Autodesk Fusion 360 part; units mm, degrees
(part 16 of 28)
  line L828 (140.495, -16.335) -> (140.495, -17.235)
  line L829 (140.045, -16.785) -> (140.945, -16.785)
  line L830 (143.9337, -15.6998) -> (144.1242, -15.6998)
  line L831 (144.1242, -15.6998) -> (144.3147, -15.7951)
  line L832 (144.3147, -15.7951) -> (144.4099, -15.8903)
  line L833 (144.4099, -15.8903) -> (144.5051, -16.0808)
  line L834 (144.5051, -16.0808) -> (144.6004, -16.4617)
  line L835 (144.6004, -16.4617) -> (144.6004, -16.9379)
  line L836 (144.6004, -16.9379) -> (144.5051, -17.3189)
  line L837 (144.5051, -17.3189) -> (144.4099, -17.5094)
  line L838 (144.4099, -17.5094) -> (144.3147, -17.6046)
  line L839 (144.3147, -17.6046) -> (144.1242, -17.6998)
  line L840 (144.1242, -17.6998) -> (143.9337, -17.6998)
  line L841 (143.9337, -17.6998) -> (143.7432, -17.6046)
  line L842 (143.7432, -17.6046) -> (143.648, -17.5094)
  line L843 (143.648, -17.5094) -> (143.5528, -17.3189)
  line L844 (143.5528, -17.3189) -> (143.4575, -16.9379)
  line L845 (143.4575, -16.9379) -> (143.4575, -16.4617)
  line L846 (143.4575, -16.4617) -> (143.5528, -16.0808)
  line L847 (143.5528, -16.0808) -> (143.648, -15.8903)
  line L848 (143.648, -15.8903) -> (143.7432, -15.7951)
  line L849 (143.7432, -15.7951) -> (143.9337, -15.6998)
  line L850 (145.4575, -17.5094) -> (145.5528, -17.6046)
  line L851 (145.5528, -17.6046) -> (145.4575, -17.6998)
  line L852 (145.4575, -17.6998) -> (145.3623, -17.6046)
  line L853 (145.3623, -17.6046) -> (145.4575, -17.5094)
  line L854 (145.4575, -17.5094) -> (145.4575, -17.6998)
  line L855 (146.5051, -17.6998) -> (146.8861, -17.6998)
  line L856 (146.8861, -17.6998) -> (147.0766, -17.6046)
  line L857 (147.0766, -17.6046) -> (147.1718, -17.5094)
  line L858 (147.1718, -17.5094) -> (147.3623, -17.2236)
  line L859 (147.3623, -17.2236) -> (147.4575, -16.8427)
  line L860 (147.4575, -16.8427) -> (147.4575, -16.0808)
  line L861 (147.4575, -16.0808) -> (147.3623, -15.8903)
  line L862 (147.3623, -15.8903) -> (147.2671, -15.7951)
  line L863 (147.2671, -15.7951) -> (147.0766, -15.6998)
  line L864 (147.0766, -15.6998) -> (146.6956, -15.6998)
  line L865 (146.6956, -15.6998) -> (146.5051, -15.7951)
  line L866 (146.5051, -15.7951) -> (146.4099, -15.8903)
  line L867 (146.4099, -15.8903) -> (146.3147, -16.0808)
  line L868 (146.3147, -16.0808) -> (146.3147, -16.557)
  line L869 (146.3147, -16.557) -> (146.4099, -16.7475)
  line L870 (146.4099, -16.7475) -> (146.5051, -16.8427)
  line L871 (146.5051, -16.8427) -> (146.6956, -16.9379)
  line L872 (146.6956, -16.9379) -> (147.0766, -16.9379)
  line L873 (147.0766, -16.9379) -> (147.2671, -16.8427)
  line L874 (147.2671, -16.8427) -> (147.3623, -16.7475)
  line L875 (147.3623, -16.7475) -> (147.4575, -16.557)
  line L876 (148.6956, -15.6998) -> (148.8861, -15.6998)
  line L877 (148.8861, -15.6998) -> (149.0766, -15.7951)
  line L878 (149.0766, -15.7951) -> (149.1718, -15.8903)
  line L879 (149.1718, -15.8903) -> (149.2671, -16.0808)
  line L880 (149.2671, -16.0808) -> (149.3623, -16.4617)
  line L881 (149.3623, -16.4617) -> (149.3623, -16.9379)
  line L882 (149.3623, -16.9379) -> (149.2671, -17.3189)
  line L883 (149.2671, -17.3189) -> (149.1718, -17.5094)
  line L884 (149.1718, -17.5094) -> (149.0766, -17.6046)
  line L885 (149.0766, -17.6046) -> (148.8861, -17.6998)
  line L886 (148.8861, -17.6998) -> (148.6956, -17.6998)
  line L887 (148.6956, -17.6998) -> (148.5051, -17.6046)
  line L888 (148.5051, -17.6046) -> (148.4099, -17.5094)
  line L889 (148.4099, -17.5094) -> (148.3147, -17.3189)
  line L890 (148.3147, -17.3189) -> (148.2194, -16.9379)
  line L891 (148.2194, -16.9379) -> (148.2194, -16.4617)
  line L892 (148.2194, -16.4617) -> (148.3147, -16.0808)
  line L893 (148.3147, -16.0808) -> (148.4099, -15.8903)
  line L894 (148.4099, -15.8903) -> (148.5051, -15.7951)
  line L895 (148.5051, -15.7951) -> (148.6956, -15.6998)
  line L896 (150.6004, -15.6998) -> (150.7909, -15.6998)
  line L897 (150.7909, -15.6998) -> (150.9813, -15.7951)
  line L898 (150.9813, -15.7951) -> (151.0766, -15.8903)
  line L899 (151.0766, -15.8903) -> (151.1718, -16.0808)
  line L900 (151.1718, -16.0808) -> (151.2671, -16.4617)
  line L901 (151.2671, -16.4617) -> (151.2671, -16.9379)
  line L902 (151.2671, -16.9379) -> (151.1718, -17.3189)
  line L903 (151.1718, -17.3189) -> (151.0766, -17.5094)
  line L904 (151.0766, -17.5094) -> (150.9813, -17.6046)
  line L905 (150.9813, -17.6046) -> (150.7909, -17.6998)
  line L906 (150.7909, -17.6998) -> (150.6004, -17.6998)
  line L907 (150.6004, -17.6998) -> (150.4099, -17.6046)
  line L908 (150.4099, -17.6046) -> (150.3147, -17.5094)
  line L909 (150.3147, -17.5094) -> (150.2194, -17.3189)
  line L910 (150.2194, -17.3189) -> (150.1242, -16.9379)
  line L911 (150.1242, -16.9379) -> (150.1242, -16.4617)
  line L912 (150.1242, -16.4617) -> (150.2194, -16.0808)
  line L913 (150.2194, -16.0808) -> (150.3147, -15.8903)
  line L914 (150.3147, -15.8903) -> (150.4099, -15.7951)
  line L915 (150.4099, -15.7951) -> (150.6004, -15.6998)
  line L916 (152.1242, -17.6998) -> (152.1242, -16.3665)
  line L917 (152.1242, -16.557) -> (152.2194, -16.4617)
  line L918 (152.2194, -16.4617) -> (152.4099, -16.3665)
  line L919 (152.4099, -16.3665) -> (152.6956, -16.3665)
  line L920 (152.6956, -16.3665) -> (152.8861, -16.4617)
  line L921 (152.8861, -16.4617) -> (152.9813, -16.6522)
  line L922 (152.9813, -16.6522) -> (152.9813, -17.6998)
  line L923 (152.9813, -16.6522) -> (153.0766, -16.4617)
  line L924 (153.0766, -16.4617) -> (153.2671, -16.3665)
  line L925 (153.2671, -16.3665) -> (153.5528, -16.3665)
  line L926 (153.5528, -16.3665) -> (153.7432, -16.4617)
  line L927 (153.7432, -16.4617) -> (153.8385, -16.6522)
  line L928 (153.8385, -16.6522) -> (153.8385, -17.6998)
  line L929 (154.7909, -17.6998) -> (154.7909, -16.3665)
  line L930 (154.7909, -16.557) -> (154.8861, -16.4617)
  line L931 (154.8861, -16.4617) -> (155.0766, -16.3665)
  line L932 (155.0766, -16.3665) -> (155.3623, -16.3665)
  line L933 (155.3623, -16.3665) -> (155.5528, -16.4617)
  line L934 (155.5528, -16.4617) -> (155.648, -16.6522)
  line L935 (155.648, -16.6522) -> (155.648, -17.6998)
  line L936 (155.648, -16.6522) -> (155.7432, -16.4617)
  line L937 (155.7432, -16.4617) -> (155.9337, -16.3665)
  line L938 (155.9337, -16.3665) -> (156.2194, -16.3665)
  line L939 (156.2194, -16.3665) -> (156.4099, -16.4617)
  line L940 (156.4099, -16.4617) -> (156.5051, -16.6522)
  line L941 (156.5052, -16.6522) -> (156.5052, -17.6998)
  line L942 (160.4099, -15.6046) -> (158.6956, -18.176)
  line L943 (162.9813, -15.6998) -> (163.1718, -15.6998)
  line L944 (163.1718, -15.6998) -> (163.3623, -15.7951)
  line L945 (163.3623, -15.7951) -> (163.4575, -15.8903)
  line L946 (163.4575, -15.8903) -> (163.5528, -16.0808)
  line L947 (163.5528, -16.0808) -> (163.648, -16.4617)
  line L948 (163.648, -16.4617) -> (163.648, -16.9379)
  line L949 (163.648, -16.9379) -> (163.5528, -17.3189)
  line L950 (163.5528, -17.3189) -> (163.4575, -17.5094)
  line L951 (163.4575, -17.5094) -> (163.3623, -17.6046)
  line L952 (163.3623, -17.6046) -> (163.1718, -17.6998)
  line L953 (163.1718, -17.6998) -> (162.9813, -17.6998)
  line L954 (162.9813, -17.6998) -> (162.7909, -17.6046)
  line L955 (162.7909, -17.6046) -> (162.6956, -17.5094)
  line L956 (162.6956, -17.5094) -> (162.6004, -17.3189)
  line L957 (162.6004, -17.3189) -> (162.5052, -16.9379)
  line L958 (162.5052, -16.9379) -> (162.5052, -16.4617)
  line L959 (162.5052, -16.4617) -> (162.6004, -16.0808)
  line L960 (162.6004, -16.0808) -> (162.6956, -15.8903)
  line L961 (162.6956, -15.8903) -> (162.7909, -15.7951)
  line L962 (162.7909, -15.7951) -> (162.9813, -15.6998)
  line L963 (164.5052, -17.5094) -> (164.6004, -17.6046)
  line L964 (164.6004, -17.6046) -> (164.5052, -17.6998)
  line L965 (164.5052, -17.6998) -> (164.4099, -17.6046)
  line L966 (164.4099, -17.6046) -> (164.5052, -17.5094)
  line L967 (164.5052, -17.5094) -> (164.5052, -17.6998)
  line L968 (165.8385, -15.6998) -> (166.029, -15.6998)
  line L969 (166.029, -15.6998) -> (166.2194, -15.7951)
  line L970 (166.2194, -15.7951) -> (166.3147, -15.8903)
  line L971 (166.3147, -15.8903) -> (166.4099, -16.0808)
  line L972 (166.4099, -16.0808) -> (166.5052, -16.4617)
  line L973 (166.5052, -16.4617) -> (166.5052, -16.9379)
  line L974 (166.5052, -16.9379) -> (166.4099, -17.3189)
  line L975 (166.4099, -17.3189) -> (166.3147, -17.5094)
  line L976 (166.3147, -17.5094) -> (166.2194, -17.6046)
  line L977 (166.2194, -17.6046) -> (166.029, -17.6998)
  line L978 (166.029, -17.6998) -> (165.8385, -17.6998)
  line L979 (165.8385, -17.6998) -> (165.648, -17.6046)
  line L980 (165.648, -17.6046) -> (165.5528, -17.5094)
  line L981 (165.5528, -17.5094) -> (165.4575, -17.3189)
  line L982 (165.4575, -17.3189) -> (165.3623, -16.9379)
  line L983 (165.3623, -16.9379) -> (165.3623, -16.4617)
  line L984 (165.3623, -16.4617) -> (165.4575, -16.0808)
  line L985 (165.4575, -16.0808) -> (165.5528, -15.8903)
  line L986 (165.5528, -15.8903) -> (165.648, -15.7951)
  line L987 (165.648, -15.7951) -> (165.8385, -15.6998)
  line L988 (167.1718, -15.6998) -> (168.4099, -15.6998)
  line L989 (168.4099, -15.6998) -> (167.7432, -16.4617)
  line L990 (167.7432, -16.4617) -> (168.029, -16.4617)
  line L991 (168.029, -16.4617) -> (168.2194, -16.557)
  line L992 (168.2194, -16.557) -> (168.3147, -16.6522)
  line L993 (168.3147, -16.6522) -> (168.4099, -16.8427)
  line L994 (168.4099, -16.8427) -> (168.4099, -17.3189)
  line L995 (168.4099, -17.3189) -> (168.3147, -17.5094)
  line L996 (168.3147, -17.5094) -> (168.2194, -17.6046)
  line L997 (168.2194, -17.6046) -> (168.029, -17.6998)
  line L998 (168.029, -17.6998) -> (167.4575, -17.6998)
  line L999 (167.4575, -17.6998) -> (167.2671, -17.6046)
  line L1000 (167.2671, -17.6046) -> (167.1718, -17.5094)
  line L1001 (170.2194, -15.6998) -> (169.2671, -15.6998)
  line L1002 (169.2671, -15.6998) -> (169.1718, -16.6522)
  line L1003 (169.1718, -16.6522) -> (169.2671, -16.557)
  line L1004 (169.2671, -16.557) -> (169.4575, -16.4617)
  line L1005 (169.4575, -16.4617) -> (169.9337, -16.4617)
  line L1006 (169.9337, -16.4617) -> (170.1242, -16.557)
  line L1007 (170.1242, -16.557) -> (170.2194, -16.6522)
  line L1008 (170.2194, -16.6522) -> (170.3147, -16.8427)
  line L1009 (170.3147, -16.8427) -> (170.3147, -17.3189)
  line L1010 (170.3147, -17.3189) -> (170.2194, -17.5094)
  line L1011 (170.2194, -17.5094) -> (170.1242, -17.6046)
  line L1012 (170.1242, -17.6046) -> (169.9337, -17.6998)
  line L1013 (169.9337, -17.6998) -> (169.4575, -17.6998)
  line L1014 (169.4575, -17.6998) -> (169.2671, -17.6046)
  line L1015 (169.2671, -17.6046) -> (169.1718, -17.5094)
  line L1016 (172.029, -16.3665) -> (172.029, -17.6998)
  line L1017 (171.5528, -15.6046) -> (171.0766, -17.0332)
  line L1018 (171.0766, -17.0332) -> (172.3147, -17.0332)
  line L1019 (172.9813, -15.6998) -> (172.9813, -16.0808)
  line L1020 (173.7432, -15.6998) -> (173.7432, -16.0808)
  line L1021 (176.6956, -18.4617) -> (176.6004, -18.3665)
  line L1022 (176.6004, -18.3665) -> (176.4099, -18.0808)
  line L1023 (176.4099, -18.0808) -> (176.3147, -17.8903)
  line L1024 (176.3147, -17.8903) -> (176.2194, -17.6046)
  line L1025 (176.2194, -17.6046) -> (176.1242, -17.1284)
  line L1026 (176.1242, -17.1284) -> (176.1242, -16.7475)
  line L1027 (176.1242, -16.7475) -> (176.2194, -16.2713)
  line L1028 (176.2194, -16.2713) -> (176.3147, -15.9856)
  line L1029 (176.3147, -15.9856) -> (176.4099, -15.7951)
  line L1030 (176.4099, -15.7951) -> (176.6004, -15.5094)
  line L1031 (176.6004, -15.5094) -> (176.6956, -15.4141)
  line L1032 (178.5052, -17.6998) -> (177.3623, -17.6998)
  line L1033 (177.9337, -17.6998) -> (177.9337, -15.6998)
  line L1034 (177.9337, -15.6998) -> (177.7432, -15.9856)
  line L1035 (177.7432, -15.9856) -> (177.5528, -16.176)
  line L1036 (177.5528, -16.176) -> (177.3623, -16.2713)
  line L1037 (179.2671, -15.8903) -> (179.3623, -15.7951)
  line L1038 (179.3623, -15.7951) -> (179.5528, -15.6998)
  line L1039 (179.5528, -15.6998) -> (180.029, -15.6998)
  line L1040 (180.029, -15.6998) -> (180.2194, -15.7951)
  line L1041 (180.2194, -15.7951) -> (180.3147, -15.8903)
  line L1042 (180.3147, -15.8903) -> (180.4099, -16.0808)
  line L1043 (180.4099, -16.0808) -> (180.4099, -16.2713)
  line L1044 (180.4099, -16.2713) -> (180.3147, -16.557)
  line L1045 (180.3147, -16.557) -> (179.1718, -17.6998)
  line L1046 (179.1718, -17.6998) -> (180.4099, -17.6998)
  line L1047 (182.7909, -17.6998) -> (182.7909, -15.6998)
  line L1048 (183.648, -17.6998) -> (183.648, -16.6522)
  line L1049 (183.648, -16.6522) -> (183.5528, -16.4617)
  line L1050 (183.5528, -16.4617) -> (183.3623, -16.3665)
  line L1051 (183.3623, -16.3665) -> (183.0766, -16.3665)
  line L1052 (183.0766, -16.3665) -> (182.8861, -16.4617)
  line L1053 (182.8861, -16.4617) -> (182.7909, -16.557)
  line L1054 (184.8861, -17.6998) -> (184.6956, -17.6046)
  line L1055 (184.6956, -17.6046) -> (184.6004, -17.5094)
  line L1056 (184.6004, -17.5094) -> (184.5052, -17.3189)
  line L1057 (184.5052, -17.3189) -> (184.5052, -16.7475)
  line L1058 (184.5052, -16.7475) -> (184.6004, -16.557)
  line L1059 (184.6004, -16.557) -> (184.6956, -16.4617)
  line L1060 (184.6956, -16.4617) -> (184.8861, -16.3665)
  line L1061 (184.8861, -16.3665) -> (185.1718, -16.3665)
  line L1062 (185.1718, -16.3665) -> (185.3623, -16.4617)
  line L1063 (185.3623, -16.4617) -> (185.4575, -16.557)
  line L1064 (185.4575, -16.557) -> (185.5528, -16.7475)
  line L1065 (185.5528, -16.7475) -> (185.5528, -17.3189)
  line L1066 (185.5528, -17.3189) -> (185.4575, -17.5094)
  line L1067 (185.4575, -17.5094) -> (185.3623, -17.6046)
  line L1068 (185.3623, -17.6046) -> (185.1718, -17.6998)
  line L1069 (185.1718, -17.6998) -> (184.8861, -17.6998)
  line L1070 (186.6956, -17.6998) -> (186.5052, -17.6046)
  line L1071 (186.5052, -17.6046) -> (186.4099, -17.4141)
  line L1072 (186.4099, -17.4141) -> (186.4099, -15.6998)
  line L1073 (188.2194, -17.6046) -> (188.029, -17.6998)
  line L1074 (188.029, -17.6998) -> (187.648, -17.6998)
  line L1075 (187.648, -17.6998) -> (187.4575, -17.6046)
  line L1076 (187.4575, -17.6046) -> (187.3623, -17.4141)
  line L1077 (187.3623, -17.4141) -> (187.3623, -16.6522)
  line L1078 (187.3623, -16.6522) -> (187.4575, -16.4617)
  line L1079 (187.4575, -16.4617) -> (187.648, -16.3665)
  line L1080 (187.648, -16.3665) -> (188.029, -16.3665)
  line L1081 (188.029, -16.3665) -> (188.2194, -16.4617)
  line L1082 (188.2194, -16.4617) -> (188.3147, -16.6522)
  line L1083 (188.3147, -16.6522) -> (188.3147, -16.8427)
  line L1084 (188.3147, -16.8427) -> (187.3623, -17.0332)
  line L1085 (189.0766, -17.6046) -> (189.2671, -17.6998)
  line L1086 (189.2671, -17.6998) -> (189.648, -17.6998)
  line L1087 (189.648, -17.6998) -> (189.8385, -17.6046)
  line L1088 (189.8385, -17.6046) -> (189.9337, -17.4141)
  line L1089 (189.9337, -17.4141) -> (189.9337, -17.3189)
  line L1090 (189.9337, -17.3189) -> (189.8385, -17.1284)
  line L1091 (189.8385, -17.1284) -> (189.648, -17.0332)
  line L1092 (189.648, -17.0332) -> (189.3623, -17.0332)
  line L1093 (189.3623, -17.0332) -> (189.1718, -16.9379)
  line L1094 (189.1718, -16.9379) -> (189.0766, -16.7475)
  line L1095 (189.0766, -16.7475) -> (189.0766, -16.6522)
  line L1096 (189.0766, -16.6522) -> (189.1718, -16.4617)
  line L1097 (189.1718, -16.4617) -> (189.3623, -16.3665)
  line L1098 (189.3623, -16.3665) -> (189.648, -16.3665)
  line L1099 (189.648, -16.3665) -> (189.8385, -16.4617)
  line L1100 (190.6004, -18.4617) -> (190.6956, -18.3665)
  line L1101 (190.6956, -18.3665) -> (190.8861, -18.0808)
  line L1102 (190.8861, -18.0808) -> (190.9813, -17.8903)
  line L1103 (190.9813, -17.8903) -> (191.0766, -17.6046)
  line L1104 (191.0766, -17.6046) -> (191.1718, -17.1284)
  line L1105 (191.1718, -17.1284) -> (191.1718, -16.7475)
  line L1106 (191.1718, -16.7475) -> (191.0766, -16.2713)
  line L1107 (191.0766, -16.2713) -> (190.9813, -15.9856)
  line L1108 (190.9813, -15.9856) -> (190.8861, -15.7951)
  line L1109 (190.8861, -15.7951) -> (190.6956, -15.5094)
  line L1110 (190.6956, -15.5094) -> (190.6004, -15.4141)
  line L1111 (140.7986, -19.7786) -> (140.7986, -19.0714)
  line L1112 (140.7986, -19.0714) -> (140.0914, -19.0714)
  line L1113 (140.0914, -19.0714) -> (140.0914, -19.7786)
  line L1114 (140.0914, -19.7786) -> (140.7986, -19.7786)
  line L1115 (144.6004, -20.3398) -> (143.4575, -20.3398)
  line L1116 (144.029, -20.3398) -> (144.029, -18.3398)
  line L1117 (144.029, -18.3398) -> (143.8385, -18.6256)
  line L1118 (143.8385, -18.6256) -> (143.648, -18.816)
  line L1119 (143.648, -18.816) -> (143.4575, -18.9113)
  line L1120 (145.4575, -20.1494) -> (145.5528, -20.2446)
  line L1121 (145.5528, -20.2446) -> (145.4575, -20.3398)
  line L1122 (145.4575, -20.3398) -> (145.3623, -20.2446)
  line L1123 (145.3623, -20.2446) -> (145.4575, -20.1494)
  line L1124 (145.4575, -20.1494) -> (145.4575, -20.3398)
  line L1125 (146.7909, -18.3398) -> (146.9813, -18.3398)
  line L1126 (146.9813, -18.3398) -> (147.1718, -18.4351)
  line L1127 (147.1718, -18.4351) -> (147.2671, -18.5303)
  line L1128 (147.2671, -18.5303) -> (147.3623, -18.7208)
  line L1129 (147.3623, -18.7208) -> (147.4575, -19.1017)
  line L1130 (147.4575, -19.1017) -> (147.4575, -19.5779)
  line L1131 (147.4575, -19.5779) -> (147.3623, -19.9589)
  line L1132 (147.3623, -19.9589) -> (147.2671, -20.1494)
  line L1133 (147.2671, -20.1494) -> (147.1718, -20.2446)
  line L1134 (147.1718, -20.2446) -> (146.9813, -20.3398)
  line L1135 (146.9813, -20.3398) -> (146.7909, -20.3398)
  line L1136 (146.7909, -20.3398) -> (146.6004, -20.2446)
  line L1137 (146.6004, -20.2446) -> (146.5051, -20.1494)
  line L1138 (146.5051, -20.1494) -> (146.4099, -19.9589)
  line L1139 (146.4099, -19.9589) -> (146.3147, -19.5779)
  line L1140 (146.3147, -19.5779) -> (146.3147, -19.1017)
  line L1141 (146.3147, -19.1017) -> (146.4099, -18.7208)
  line L1142 (146.4099, -18.7208) -> (146.5051, -18.5303)
  line L1143 (146.5051, -18.5303) -> (146.6004, -18.4351)
  line L1144 (146.6004, -18.4351) -> (146.7909, -18.3398)
  line L1145 (148.6956, -18.3398) -> (148.8861, -18.3398)
  line L1146 (148.8861, -18.3398) -> (149.0766, -18.4351)
  line L1147 (149.0766, -18.4351) -> (149.1718, -18.5303)
  line L1148 (149.1718, -18.5303) -> (149.2671, -18.7208)
  line L1149 (149.2671, -18.7208) -> (149.3623, -19.1017)
  line L1150 (149.3623, -19.1017) -> (149.3623, -19.5779)
  line L1151 (149.3623, -19.5779) -> (149.2671, -19.9589)
  line L1152 (149.2671, -19.9589) -> (149.1718, -20.1494)
  line L1153 (149.1718, -20.1494) -> (149.0766, -20.2446)
  line L1154 (149.0766, -20.2446) -> (148.8861, -20.3398)
  line L1155 (148.8861, -20.3398) -> (148.6956, -20.3398)
  line L1156 (148.6956, -20.3398) -> (148.5051, -20.2446)
  line L1157 (148.5051, -20.2446) -> (148.4099, -20.1494)
  line L1158 (148.4099, -20.1494) -> (148.3147, -19.9589)
  line L1159 (148.3147, -19.9589) -> (148.2194, -19.5779)
  line L1160 (148.2194, -19.5779) -> (148.2194, -19.1017)
  line L1161 (148.2194, -19.1017) -> (148.3147, -18.7208)
  line L1162 (148.3147, -18.7208) -> (148.4099, -18.5303)
  line L1163 (148.4099, -18.5303) -> (148.5051, -18.4351)
  line L1164 (148.5051, -18.4351) -> (148.6956, -18.3398)
  line L1165 (150.6004, -18.3398) -> (150.7909, -18.3398)
  line L1166 (150.7909, -18.3398) -> (150.9813, -18.4351)
  line L1167 (150.9813, -18.4351) -> (151.0766, -18.5303)
  line L1168 (151.0766, -18.5303) -> (151.1718, -18.7208)
  line L1169 (151.1718, -18.7208) -> (151.2671, -19.1017)
  line L1170 (151.2671, -19.1017) -> (151.2671, -19.5779)
  line L1171 (151.2671, -19.5779) -> (151.1718, -19.9589)
  line L1172 (151.1718, -19.9589) -> (151.0766, -20.1494)
  line L1173 (151.0766, -20.1494) -> (150.9813, -20.2446)
  line L1174 (150.9813, -20.2446) -> (150.7909, -20.3398)
  line L1175 (150.7909, -20.3398) -> (150.6004, -20.3398)
  line L1176 (150.6004, -20.3398) -> (150.4099, -20.2446)
  line L1177 (150.4099, -20.2446) -> (150.3147, -20.1494)
  line L1178 (150.3147, -20.1494) -> (150.2194, -19.9589)
  line L1179 (150.2194, -19.9589) -> (150.1242, -19.5779)
  line L1180 (150.1242, -19.5779) -> (150.1242, -19.1017)
  line L1181 (150.1242, -19.1017) -> (150.2194, -18.7208)
  line L1182 (150.2194, -18.7208) -> (150.3147, -18.5303)
  line L1183 (150.3147, -18.5303) -> (150.4099, -18.4351)
  line L1184 (150.4099, -18.4351) -> (150.6004, -18.3398)
  line L1185 (152.1242, -20.3398) -> (152.1242, -19.0065)
  line L1186 (152.1242, -19.197) -> (152.2194, -19.1017)
  line L1187 (152.2194, -19.1017) -> (152.4099, -19.0065)
  line L1188 (152.4099, -19.0065) -> (152.6956, -19.0065)
  line L1189 (152.6956, -19.0065) -> (152.8861, -19.1017)
  line L1190 (152.8861, -19.1017) -> (152.9813, -19.2922)
  line L1191 (152.9813, -19.2922) -> (152.9813, -20.3398)
  line L1192 (152.9813, -19.2922) -> (153.0766, -19.1017)
  line L1193 (153.0766, -19.1017) -> (153.2671, -19.0065)
  line L1194 (153.2671, -19.0065) -> (153.5528, -19.0065)
  line L1195 (153.5528, -19.0065) -> (153.7432, -19.1017)
  line L1196 (153.7432, -19.1017) -> (153.8385, -19.2922)
  line L1197 (153.8385, -19.2922) -> (153.8385, -20.3398)
  line L1198 (154.7909, -20.3398) -> (154.7909, -19.0065)
  line L1199 (154.7909, -19.197) -> (154.8861, -19.1017)
  line L1200 (154.8861, -19.1017) -> (155.0766, -19.0065)
  line L1201 (155.0766, -19.0065) -> (155.3623, -19.0065)
  line L1202 (155.3623, -19.0065) -> (155.5528, -19.1017)
  line L1203 (155.5528, -19.1017) -> (155.648, -19.2922)
  line L1204 (155.648, -19.2922) -> (155.648, -20.3398)
  line L1205 (155.648, -19.2922) -> (155.7432, -19.1017)
  line L1206 (155.7432, -19.1017) -> (155.9337, -19.0065)
  line L1207 (155.9337, -19.0065) -> (156.2194, -19.0065)
  line L1208 (156.2194, -19.0065) -> (156.4099, -19.1017)
  line L1209 (156.4099, -19.1017) -> (156.5051, -19.2922)
  line L1210 (156.5052, -19.2922) -> (156.5052, -20.3398)
  line L1211 (160.4099, -18.2446) -> (158.6956, -20.816)
  line L1212 (162.9813, -18.3398) -> (163.1718, -18.3398)
  line L1213 (163.1718, -18.3398) -> (163.3623, -18.4351)
  line L1214 (163.3623, -18.4351) -> (163.4575, -18.5303)
  line L1215 (163.4575, -18.5303) -> (163.5528, -18.7208)
  line L1216 (163.5528, -18.7208) -> (163.648, -19.1017)
  line L1217 (163.648, -19.1017) -> (163.648, -19.5779)
  line L1218 (163.648, -19.5779) -> (163.5528, -19.9589)
  line L1219 (163.5528, -19.9589) -> (163.4575, -20.1494)
  line L1220 (163.4575, -20.1494) -> (163.3623, -20.2446)
  line L1221 (163.3623, -20.2446) -> (163.1718, -20.3398)
  line L1222 (163.1718, -20.3398) -> (162.9813, -20.3398)
  line L1223 (162.9813, -20.3398) -> (162.7909, -20.2446)
  line L1224 (162.7909, -20.2446) -> (162.6956, -20.1494)
  line L1225 (162.6956, -20.1494) -> (162.6004, -19.9589)
  line L1226 (162.6004, -19.9589) -> (162.5052, -19.5779)
  line L1227 (162.5052, -19.5779) -> (162.5052, -19.1017)
  line L1228 (162.5052, -19.1017) -> (162.6004, -18.7208)
  line L1229 (162.6004, -18.7208) -> (162.6956, -18.5303)
  line L1230 (162.6956, -18.5303) -> (162.7909, -18.4351)
  line L1231 (162.7909, -18.4351) -> (162.9813, -18.3398)
  line L1232 (164.5052, -20.1494) -> (164.6004, -20.2446)
  line L1233 (164.6004, -20.2446) -> (164.5052, -20.3398)
  line L1234 (164.5052, -20.3398) -> (164.4099, -20.2446)
  line L1235 (164.4099, -20.2446) -> (164.5052, -20.1494)
  line L1236 (164.5052, -20.1494) -> (164.5052, -20.3398)
  line L1237 (165.8385, -18.3398) -> (166.029, -18.3398)
  line L1238 (166.029, -18.3398) -> (166.2194, -18.4351)
  line L1239 (166.2194, -18.4351) -> (166.3147, -18.5303)
  line L1240 (166.3147, -18.5303) -> (166.4099, -18.7208)
  line L1241 (166.4099, -18.7208) -> (166.5052, -19.1017)
  line L1242 (166.5052, -19.1017) -> (166.5052, -19.5779)
  line L1243 (166.5052, -19.5779) -> (166.4099, -19.9589)
  line L1244 (166.4099, -19.9589) -> (166.3147, -20.1494)
  line L1245 (166.3147, -20.1494) -> (166.2194, -20.2446)
  line L1246 (166.2194, -20.2446) -> (166.029, -20.3398)
  line L1247 (166.029, -20.3398) -> (165.8385, -20.3398)
  line L1248 (165.8385, -20.3398) -> (165.648, -20.2446)
  line L1249 (165.648, -20.2446) -> (165.5528, -20.1494)
  line L1250 (165.5528, -20.1494) -> (165.4575, -19.9589)
  line L1251 (165.4575, -19.9589) -> (165.3623, -19.5779)
  line L1252 (165.3623, -19.5779) -> (165.3623, -19.1017)
  line L1253 (165.3623, -19.1017) -> (165.4575, -18.7208)
  line L1254 (165.4575, -18.7208) -> (165.5528, -18.5303)
  line L1255 (165.5528, -18.5303) -> (165.648, -18.4351)
  line L1256 (165.648, -18.4351) -> (165.8385, -18.3398)
  line L1257 (167.1718, -18.3398) -> (168.4099, -18.3398)
  line L1258 (168.4099, -18.3398) -> (167.7432, -19.1017)
  line L1259 (167.7432, -19.1017) -> (168.029, -19.1017)
  line L1260 (168.029, -19.1017) -> (168.2194, -19.197)
  line L1261 (168.2194, -19.197) -> (168.3147, -19.2922)
  line L1262 (168.3147, -19.2922) -> (168.4099, -19.4827)
  line L1263 (168.4099, -19.4827) -> (168.4099, -19.9589)
  line L1264 (168.4099, -19.9589) -> (168.3147, -20.1494)
  line L1265 (168.3147, -20.1494) -> (168.2194, -20.2446)
  line L1266 (168.2194, -20.2446) -> (168.029, -20.3398)
  line L1267 (168.029, -20.3398) -> (167.4575, -20.3398)
  line L1268 (167.4575, -20.3398) -> (167.2671, -20.2446)
  line L1269 (167.2671, -20.2446) -> (167.1718, -20.1494)
  line L1270 (169.3623, -20.3398) -> (169.7432, -20.3398)
  line L1271 (169.7432, -20.3398) -> (169.9337, -20.2446)
  line L1272 (169.9337, -20.2446) -> (170.029, -20.1494)
  line L1273 (170.029, -20.1494) -> (170.2194, -19.8636)
  line L1274 (170.2194, -19.8636) -> (170.3147, -19.4827)
  line L1275 (170.3147, -19.4827) -> (170.3147, -18.7208)
  line L1276 (170.3147, -18.7208) -> (170.2194, -18.5303)
  line L1277 (170.2194, -18.5303) -> (170.1242, -18.4351)
  line L1278 (170.1242, -18.4351) -> (169.9337, -18.3398)
  line L1279 (169.9337, -18.3398) -> (169.5528, -18.3398)
  line L1280 (169.5528, -18.3398) -> (169.3623, -18.4351)
  line L1281 (169.3623, -18.4351) -> (169.2671, -18.5303)
  line L1282 (169.2671, -18.5303) -> (169.1718, -18.7208)
  line L1283 (169.1718, -18.7208) -> (169.1718, -19.197)
  line L1284 (169.1718, -19.197) -> (169.2671, -19.3875)
  line L1285 (169.2671, -19.3875) -> (169.3623, -19.4827)
  line L1286 (169.3623, -19.4827) -> (169.5528, -19.5779)
  line L1287 (169.5528, -19.5779) -> (169.9337, -19.5779)
  line L1288 (169.9337, -19.5779) -> (170.1242, -19.4827)
  line L1289 (170.1242, -19.4827) -> (170.2194, -19.3875)
  line L1290 (170.2194, -19.3875) -> (170.3147, -19.197)
  line L1291 (172.029, -19.0065) -> (172.029, -20.3398)
  line L1292 (171.5528, -18.2446) -> (171.0766, -19.6732)
  line L1293 (171.0766, -19.6732) -> (172.3147, -19.6732)
  line L1294 (172.9813, -18.3398) -> (172.9813, -18.7208)
  line L1295 (173.7432, -18.3398) -> (173.7432, -18.7208)
  line L1296 (176.6956, -21.1017) -> (176.6004, -21.0065)
  line L1297 (176.6004, -21.0065) -> (176.4099, -20.7208)
  line L1298 (176.4099, -20.7208) -> (176.3147, -20.5303)
  line L1299 (176.3147, -20.5303) -> (176.2194, -20.2446)
  line L1300 (176.2194, -20.2446) -> (176.1242, -19.7684)
  line L1301 (176.1242, -19.7684) -> (176.1242, -19.3875)
  line L1302 (176.1242, -19.3875) -> (176.2194, -18.9113)
  line L1303 (176.2194, -18.9113) -> (176.3147, -18.6256)
  line L1304 (176.3147, -18.6256) -> (176.4099, -18.4351)
  line L1305 (176.4099, -18.4351) -> (176.6004, -18.1494)
  line L1306 (176.6004, -18.1494) -> (176.6956, -18.0541)
  line L1307 (178.5052, -20.3398) -> (177.3623, -20.3398)
  line L1308 (177.9337, -20.3398) -> (177.9337, -18.3398)
  line L1309 (177.9337, -18.3398) -> (177.7432, -18.6256)
  line L1310 (177.7432, -18.6256) -> (177.5528, -18.816)
  line L1311 (177.5528, -18.816) -> (177.3623, -18.9113)
  line L1312 (179.2671, -18.5303) -> (179.3623, -18.4351)
  line L1313 (179.3623, -18.4351) -> (179.5528, -18.3398)
  line L1314 (179.5528, -18.3398) -> (180.029, -18.3398)
  line L1315 (180.029, -18.3398) -> (180.2194, -18.4351)
  line L1316 (180.2194, -18.4351) -> (180.3147, -18.5303)
  line L1317 (180.3147, -18.5303) -> (180.4099, -18.7208)
  line L1318 (180.4099, -18.7208) -> (180.4099, -18.9113)
  line L1319 (180.4099, -18.9113) -> (180.3147, -19.197)
  line L1320 (180.3147, -19.197) -> (179.1718, -20.3398)
  line L1321 (179.1718, -20.3398) -> (180.4099, -20.3398)
  line L1322 (182.7909, -20.3398) -> (182.7909, -18.3398)
  line L1323 (183.648, -20.3398) -> (183.648, -19.2922)
  line L1324 (183.648, -19.2922) -> (183.5528, -19.1017)
  line L1325 (183.5528, -19.1017) -> (183.3623, -19.0065)
  line L1326 (183.3623, -19.0065) -> (183.0766, -19.0065)
  line L1327 (183.0766, -19.0065) -> (182.8861, -19.1017)
  line L1328 (182.8861, -19.1017) -> (182.7909, -19.197)
  line L1329 (184.8861, -20.3398) -> (184.6956, -20.2446)
  line L1330 (184.6956, -20.2446) -> (184.6004, -20.1494)
  line L1331 (184.6004, -20.1494) -> (184.5052, -19.9589)
  line L1332 (184.5052, -19.9589) -> (184.5052, -19.3875)
  line L1333 (184.5052, -19.3875) -> (184.6004, -19.197)
  line L1334 (184.6004, -19.197) -> (184.6956, -19.1017)
  line L1335 (184.6956, -19.1017) -> (184.8861, -19.0065)
  line L1336 (184.8861, -19.0065) -> (185.1718, -19.0065)
  line L1337 (185.1718, -19.0065) -> (185.3623, -19.1017)
  line L1338 (185.3623, -19.1017) -> (185.4575, -19.197)
  line L1339 (185.4575, -19.197) -> (185.5528, -19.3875)
  line L1340 (185.5528, -19.3875) -> (185.5528, -19.9589)
  line L1341 (185.5528, -19.9589) -> (185.4575, -20.1494)
  line L1342 (185.4575, -20.1494) -> (185.3623, -20.2446)
  line L1343 (185.3623, -20.2446) -> (185.1718, -20.3398)
  line L1344 (185.1718, -20.3398) -> (184.8861, -20.3398)
  line L1345 (186.6956, -20.3398) -> (186.5052, -20.2446)
  line L1346 (186.5052, -20.2446) -> (186.4099, -20.0541)
  line L1347 (186.4099, -20.0541) -> (186.4099, -18.3398)
  line L1348 (188.2194, -20.2446) -> (188.029, -20.3398)
  line L1349 (188.029, -20.3398) -> (187.648, -20.3398)
  line L1350 (187.648, -20.3398) -> (187.4575, -20.2446)
  line L1351 (187.4575, -20.2446) -> (187.3623, -20.0541)
  line L1352 (187.3623, -20.0541) -> (187.3623, -19.2922)
  line L1353 (187.3623, -19.2922) -> (187.4575, -19.1017)
  line L1354 (187.4575, -19.1017) -> (187.648, -19.0065)
  line L1355 (187.648, -19.0065) -> (188.029, -19.0065)
  line L1356 (188.029, -19.0065) -> (188.2194, -19.1017)
  line L1357 (188.2194, -19.1017) -> (188.3147, -19.2922)
  line L1358 (188.3147, -19.2922) -> (188.3147, -19.4827)
  line L1359 (188.3147, -19.4827) -> (187.3623, -19.6732)
  line L1360 (189.0766, -20.2446) -> (189.2671, -20.3398)
  line L1361 (189.2671, -20.3398) -> (189.648, -20.3398)
  line L1362 (189.648, -20.3398) -> (189.8385, -20.2446)
  line L1363 (189.8385, -20.2446) -> (189.9337, -20.0541)
  line L1364 (189.9337, -20.0541) -> (189.9337, -19.9589)
  line L1365 (189.9337, -19.9589) -> (189.8385, -19.7684)
  line L1366 (189.8385, -19.7684) -> (189.648, -19.6732)
  line L1367 (189.648, -19.6732) -> (189.3623, -19.6732)
  line L1368 (189.3623, -19.6732) -> (189.1718, -19.5779)
  line L1369 (189.1718, -19.5779) -> (189.0766, -19.3875)
  line L1370 (189.0766, -19.3875) -> (189.0766, -19.2922)
  line L1371 (189.0766, -19.2922) -> (189.1718, -19.1017)
  line L1372 (189.1718, -19.1017) -> (189.3623, -19.0065)
  line L1373 (189.3623, -19.0065) -> (189.648, -19.0065)
  line L1374 (189.648, -19.0065) -> (189.8385, -19.1017)
  line L1375 (190.6004, -21.1017) -> (190.6956, -21.0065)
  line L1376 (190.6956, -21.0065) -> (190.8861, -20.7208)
  line L1377 (190.8861, -20.7208) -> (190.9813, -20.5303)
  line L1378 (190.9813, -20.5303) -> (191.0766, -20.2446)
  line L1379 (191.0766, -20.2446) -> (191.1718, -19.7684)
  line L1380 (191.1718, -19.7684) -> (191.1718, -19.3875)
  line L1381 (191.1718, -19.3875) -> (191.0766, -18.9113)
  line L1382 (191.0766, -18.9113) -> (190.9813, -18.6256)
  line L1383 (190.9813, -18.6256) -> (190.8861, -18.4351)
  line L1384 (190.8861, -18.4351) -> (190.6956, -18.1494)
  line L1385 (190.6956, -18.1494) -> (190.6004, -18.0541)
extrude "Extrude4" cut sketch "Blinking Light House-PTH-drl_map" against normal blind 1.778 contours A53
sketch "Sketch10" plane through (0, 0, 0) normal (0, 0, 1) x (1, 0, 0)
  line L0 (149.1234, 3.81) -> (147.0282, 3.81)
  circle A0 centre (149.1234, 3.81) radius 2.0955
  line L1 (149.1234, 3.81) -> (3.2766, 3.81)
  circle A1 centre (3.2766, 3.81) radius 2.0955
  dimension "d157" = 4.191
  dimension "d158" = 145.8468
  dimension "d159" = 4.191
  constraint horizontal L0
  constraint coincident L0.start A0.centre
  constraint parallel L0 L1
  constraint coincident L1.end A1.centre
  measures "d157" diameter of A0
  measures "d158" distance of L0.start L1.end
  measures "d159" diameter of A1
sketch "Blinking Light House-F_Cu (1)" plane through (0, 0, 1.4859) normal (0, 0, 1) x (1, 0, 0)
  line L0 (53.0356, 12.7635) -> (53.2293, 12.7328)
  line L1 (53.2293, 12.7328) -> (53.4159, 12.6722)
  line L2 (53.4159, 12.6722) -> (53.5907, 12.5831)
  line L3 (53.5907, 12.5831) -> (53.7493, 12.4678)
  line L4 (53.7493, 12.4678) -> (53.888, 12.3291)
  line L5 (53.888, 12.3291) -> (54.0033, 12.1704)
  line L6 (54.0033, 12.1704) -> (54.0924, 11.9957)
  line L7 (54.0924, 11.9957) -> (54.153, 11.8091)
  line L8 (54.153, 11.8091) -> (54.1837, 11.6154)
  line L9 (54.1837, 11.6154) -> (54.1837, 11.4192)
  line L10 (54.1837, 11.4192) -> (54.153, 11.2255)
  line L11 (54.153, 11.2255) -> (54.0924, 11.039)
  line L12 (54.0924, 11.039) -> (54.0033, 10.8642)
  line L13 (54.0033, 10.8642) -> (53.888, 10.7055)
  line L14 (53.888, 10.7055) -> (53.7493, 10.5668)
  line L15 (53.7493, 10.5668) -> (53.5907, 10.4515)
  line L16 (53.5907, 10.4515) -> (53.4159, 10.3625)
  line L17 (53.4159, 10.3625) -> (53.2293, 10.3018)
  line L18 (53.2293, 10.3018) -> (53.0356, 10.2712)
  line L19 (53.0356, 10.2712) -> (52.9375, 10.2673)
  line L20 (52.9375, 10.2673) -> (52.4375, 10.2673)
  line L21 (52.4375, 10.2673) -> (52.3395, 10.2712)
  line L22 (52.3395, 10.2712) -> (52.1457, 10.3018)
  line L23 (52.1457, 10.3018) -> (51.9592, 10.3625)
  line L24 (51.9592, 10.3625) -> (51.7844, 10.4515)
  line L25 (51.7844, 10.4515) -> (51.6257, 10.5668)
  line L26 (51.6257, 10.5668) -> (51.487, 10.7055)
  line L27 (51.487, 10.7055) -> (51.3717, 10.8642)
  line L28 (51.3717, 10.8642) -> (51.2827, 11.039)
  line L29 (51.2827, 11.039) -> (51.2221, 11.2255)
  line L30 (51.2221, 11.2255) -> (51.1914, 11.4192)
  line L31 (51.1914, 11.4192) -> (51.1914, 11.6154)
  line L32 (51.1914, 11.6154) -> (51.2221, 11.8091)
  line L33 (51.2221, 11.8091) -> (51.2827, 11.9957)
  line L34 (51.2827, 11.9957) -> (51.3717, 12.1704)
  line L35 (51.3717, 12.1704) -> (51.487, 12.3291)
  line L36 (51.487, 12.3291) -> (51.6257, 12.4678)
  line L37 (51.6257, 12.4678) -> (51.7844, 12.5831)
  line L38 (51.7844, 12.5831) -> (51.9592, 12.6722)
  line L39 (51.9592, 12.6722) -> (52.1457, 12.7328)
  line L40 (52.1457, 12.7328) -> (52.3395, 12.7635)
  line L41 (52.3395, 12.7635) -> (52.4375, 12.7673)
  line L42 (52.4375, 12.7673) -> (52.9375, 12.7673)
  line L43 (52.9375, 12.7673) -> (53.0356, 12.7635)
  line L44 (60.6556, 12.7635) -> (60.8493, 12.7328)
  line L45 (60.8493, 12.7328) -> (61.0359, 12.6722)
  line L46 (61.0359, 12.6722) -> (61.2107, 12.5831)
  line L47 (61.2107, 12.5831) -> (61.3693, 12.4678)
  line L48 (61.3693, 12.4678) -> (61.508, 12.3291)
  line L49 (61.508, 12.3291) -> (61.6233, 12.1704)
  line L50 (61.6233, 12.1704) -> (61.7124, 11.9957)
  line L51 (61.7124, 11.9957) -> (61.773, 11.8091)
  line L52 (61.773, 11.8091) -> (61.8037, 11.6154)
  line L53 (61.8037, 11.6154) -> (61.8037, 11.4192)
  line L54 (61.8037, 11.4192) -> (61.773, 11.2255)
  line L55 (61.773, 11.2255) -> (61.7124, 11.039)
  line L56 (61.7124, 11.039) -> (61.6233, 10.8642)
  line L57 (61.6233, 10.8642) -> (61.508, 10.7055)
  line L58 (61.508, 10.7055) -> (61.3693, 10.5668)
  line L59 (61.3693, 10.5668) -> (61.2107, 10.4515)
  line L60 (61.2107, 10.4515) -> (61.0359, 10.3625)
  line L61 (61.0359, 10.3625) -> (60.8493, 10.3018)
  line L62 (60.8493, 10.3018) -> (60.6556, 10.2712)
  line L63 (60.6556, 10.2712) -> (60.5575, 10.2673)
  line L64 (60.5575, 10.2673) -> (60.0575, 10.2673)
  line L65 (60.0575, 10.2673) -> (59.9595, 10.2712)
  line L66 (59.9595, 10.2712) -> (59.7657, 10.3018)
  line L67 (59.7657, 10.3018) -> (59.5792, 10.3625)
  line L68 (59.5792, 10.3625) -> (59.4044, 10.4515)
  line L69 (59.4044, 10.4515) -> (59.2457, 10.5668)
  line L70 (59.2457, 10.5668) -> (59.107, 10.7055)
  line L71 (59.107, 10.7055) -> (58.9917, 10.8642)
  line L72 (58.9917, 10.8642) -> (58.9027, 11.039)
  line L73 (58.9027, 11.039) -> (58.8421, 11.2255)
  line L74 (58.8421, 11.2255) -> (58.8114, 11.4192)
  line L75 (58.8114, 11.4192) -> (58.8114, 11.6154)
  line L76 (58.8114, 11.6154) -> (58.8421, 11.8091)
  line L77 (58.8421, 11.8091) -> (58.9027, 11.9957)
  line L78 (58.9027, 11.9957) -> (58.9917, 12.1704)
  line L79 (58.9917, 12.1704) -> (59.107, 12.3291)
  line L80 (59.107, 12.3291) -> (59.2457, 12.4678)
  line L81 (59.2457, 12.4678) -> (59.4044, 12.5831)
  line L82 (59.4044, 12.5831) -> (59.5792, 12.6722)
  line L83 (59.5792, 12.6722) -> (59.7657, 12.7328)
  line L84 (59.7657, 12.7328) -> (59.9595, 12.7635)
  line L85 (59.9595, 12.7635) -> (60.0575, 12.7673)
  line L86 (60.0575, 12.7673) -> (60.5575, 12.7673)
  line L87 (60.5575, 12.7673) -> (60.6556, 12.7635)
  line L88 (113.9956, 12.7635) -> (114.1893, 12.7328)
  line L89 (114.1893, 12.7328) -> (114.3759, 12.6722)
  line L90 (114.3759, 12.6722) -> (114.5507, 12.5831)
  line L91 (114.5507, 12.5831) -> (114.7093, 12.4678)
  line L92 (114.7093, 12.4678) -> (114.848, 12.3291)
  line L93 (114.848, 12.3291) -> (114.9633, 12.1704)
  line L94 (114.9633, 12.1704) -> (115.0524, 11.9957)
  line L95 (115.0524, 11.9957) -> (115.113, 11.8091)
  line L96 (115.113, 11.8091) -> (115.1437, 11.6154)
  line L97 (115.1437, 11.6154) -> (115.1437, 11.4192)
  line L98 (115.1437, 11.4192) -> (115.113, 11.2255)
  line L99 (115.113, 11.2255) -> (115.0524, 11.039)
  line L100 (115.0524, 11.039) -> (114.9633, 10.8642)
  line L101 (114.9633, 10.8642) -> (114.848, 10.7055)
  line L102 (114.848, 10.7055) -> (114.7093, 10.5668)
  line L103 (114.7093, 10.5668) -> (114.5507, 10.4515)
  line L104 (114.5507, 10.4515) -> (114.3759, 10.3625)
  line L105 (114.3759, 10.3625) -> (114.1893, 10.3018)
  line L106 (114.1893, 10.3018) -> (113.9956, 10.2712)
  line L107 (113.9956, 10.2712) -> (113.8975, 10.2673)
  line L108 (113.8975, 10.2673) -> (113.3975, 10.2673)
  line L109 (113.3975, 10.2673) -> (113.2995, 10.2712)
  line L110 (113.2995, 10.2712) -> (113.1057, 10.3018)
  line L111 (113.1057, 10.3018) -> (112.9192, 10.3625)
  line L112 (112.9192, 10.3625) -> (112.7444, 10.4515)
  line L113 (112.7444, 10.4515) -> (112.5857, 10.5668)
  line L114 (112.5857, 10.5668) -> (112.447, 10.7055)
  line L115 (112.447, 10.7055) -> (112.3317, 10.8642)
  line L116 (112.3317, 10.8642) -> (112.2427, 11.039)
  line L117 (112.2427, 11.039) -> (112.1821, 11.2255)
  line L118 (112.1821, 11.2255) -> (112.1514, 11.4192)
  line L119 (112.1514, 11.4192) -> (112.1514, 11.6154)
  line L120 (112.1514, 11.6154) -> (112.1821, 11.8091)
  line L121 (112.1821, 11.8091) -> (112.2427, 11.9957)
  line L122 (112.2427, 11.9957) -> (112.3317, 12.1704)
  line L123 (112.3317, 12.1704) -> (112.447, 12.3291)
  line L124 (112.447, 12.3291) -> (112.5857, 12.4678)
  line L125 (112.5857, 12.4678) -> (112.7444, 12.5831)
  line L126 (112.7444, 12.5831) -> (112.9192, 12.6722)
  line L127 (112.9192, 12.6722) -> (113.1057, 12.7328)
  line L128 (113.1057, 12.7328) -> (113.2995, 12.7635)
  line L129 (113.2995, 12.7635) -> (113.3975, 12.7673)
  line L130 (113.3975, 12.7673) -> (113.8975, 12.7673)
  line L131 (113.8975, 12.7673) -> (113.9956, 12.7635)
  line L132 (121.6156, 12.7635) -> (121.8093, 12.7328)
  line L133 (121.8093, 12.7328) -> (121.9959, 12.6722)
  line L134 (121.9959, 12.6722) -> (122.1707, 12.5831)
  line L135 (122.1707, 12.5831) -> (122.3293, 12.4678)
  line L136 (122.3293, 12.4678) -> (122.468, 12.3291)
  line L137 (122.468, 12.3291) -> (122.5833, 12.1704)
  line L138 (122.5833, 12.1704) -> (122.6724, 11.9957)
  line L139 (122.6724, 11.9957) -> (122.733, 11.8091)
  line L140 (122.733, 11.8091) -> (122.7637, 11.6154)
  line L141 (122.7637, 11.6154) -> (122.7637, 11.4192)
  line L142 (122.7637, 11.4192) -> (122.733, 11.2255)
  line L143 (122.733, 11.2255) -> (122.6724, 11.039)
  line L144 (122.6724, 11.039) -> (122.5833, 10.8642)
  line L145 (122.5833, 10.8642) -> (122.468, 10.7055)
  line L146 (122.468, 10.7055) -> (122.3293, 10.5668)
  line L147 (122.3293, 10.5668) -> (122.1707, 10.4515)
  line L148 (122.1707, 10.4515) -> (121.9959, 10.3625)
  line L149 (121.9959, 10.3625) -> (121.8093, 10.3018)
  line L150 (121.8093, 10.3018) -> (121.6156, 10.2712)
  line L151 (121.6156, 10.2712) -> (121.5175, 10.2673)
  line L152 (121.5175, 10.2673) -> (121.0175, 10.2673)
  line L153 (121.0175, 10.2673) -> (120.9195, 10.2712)
  line L154 (120.9195, 10.2712) -> (120.7257, 10.3018)
  line L155 (120.7257, 10.3018) -> (120.5392, 10.3625)
  line L156 (120.5392, 10.3625) -> (120.3644, 10.4515)
  line L157 (120.3644, 10.4515) -> (120.2057, 10.5668)
  line L158 (120.2057, 10.5668) -> (120.067, 10.7055)
  line L159 (120.067, 10.7055) -> (119.9517, 10.8642)
  line L160 (119.9517, 10.8642) -> (119.8627, 11.039)
  line L161 (119.8627, 11.039) -> (119.8021, 11.2255)
  line L162 (119.8021, 11.2255) -> (119.7714, 11.4192)
  line L163 (119.7714, 11.4192) -> (119.7714, 11.6154)
  line L164 (119.7714, 11.6154) -> (119.8021, 11.8091)
  line L165 (119.8021, 11.8091) -> (119.8627, 11.9957)
  line L166 (119.8627, 11.9957) -> (119.9517, 12.1704)
  line L167 (119.9517, 12.1704) -> (120.067, 12.3291)
  line L168 (120.067, 12.3291) -> (120.2057, 12.4678)
  line L169 (120.2057, 12.4678) -> (120.3644, 12.5831)
  line L170 (120.3644, 12.5831) -> (120.5392, 12.6722)
  line L171 (120.5392, 12.6722) -> (120.7257, 12.7328)
  line L172 (120.7257, 12.7328) -> (120.9195, 12.7635)
  line L173 (120.9195, 12.7635) -> (121.0175, 12.7673)
  line L174 (121.0175, 12.7673) -> (121.5175, 12.7673)
  line L175 (121.5175, 12.7673) -> (121.6156, 12.7635)
  line L176 (29.6898, 13.6131) -> (29.8835, 13.5824)
  line L177 (29.8835, 13.5824) -> (30.0701, 13.5218)
  line L178 (30.0701, 13.5218) -> (30.2449, 13.4328)
  line L179 (30.2449, 13.4328) -> (30.4036, 13.3175)
  line L180 (30.4036, 13.3175) -> (30.5422, 13.1788)
  line L181 (30.5422, 13.1788) -> (30.6575, 13.0201)
  line L182 (30.6575, 13.0201) -> (30.7466, 12.8453)
  line L183 (30.7466, 12.8453) -> (30.8072, 12.6588)
  line L184 (30.8072, 12.6588) -> (30.8379, 12.465)
  line L185 (30.8379, 12.465) -> (30.8379, 12.2689)
  line L186 (30.8379, 12.2689) -> (30.8072, 12.0752)
  line L187 (30.8072, 12.0752) -> (30.7466, 11.8886)
  line L188 (30.7466, 11.8886) -> (30.6575, 11.7138)
  line L189 (30.6575, 11.7138) -> (30.5422, 11.5551)
  line L190 (30.5422, 11.5551) -> (30.4036, 11.4165)
  line L191 (30.4036, 11.4165) -> (30.2449, 11.3012)
  line L192 (30.2449, 11.3012) -> (30.0701, 11.2121)
  line L193 (30.0701, 11.2121) -> (29.8835, 11.1515)
  line L194 (29.8835, 11.1515) -> (29.6898, 11.1208)
  line L195 (29.6898, 11.1208) -> (29.5917, 11.117)
  line L196 (29.5917, 11.117) -> (29.0917, 11.117)
  line L197 (29.0917, 11.117) -> (28.9937, 11.1208)
  line L198 (28.9937, 11.1208) -> (28.7999, 11.1515)
  line L199 (28.7999, 11.1515) -> (28.6134, 11.2121)
  line L200 (28.6134, 11.2121) -> (28.4386, 11.3012)
  line L201 (28.4386, 11.3012) -> (28.2799, 11.4165)
  line L202 (28.2799, 11.4165) -> (28.1412, 11.5551)
  line L203 (28.1412, 11.5551) -> (28.0259, 11.7138)
  line L204 (28.0259, 11.7138) -> (27.9369, 11.8886)
  line L205 (27.9369, 11.8886) -> (27.8763, 12.0751)
  line L206 (27.8763, 12.0751) -> (27.8456, 12.2689)
  line L207 (27.8456, 12.2689) -> (27.8456, 12.465)
  line L208 (27.8456, 12.465) -> (27.8763, 12.6588)
  line L209 (27.8763, 12.6588) -> (27.9369, 12.8453)
  line L210 (27.9369, 12.8453) -> (28.0259, 13.0201)
  line L211 (28.0259, 13.0201) -> (28.1412, 13.1788)
  line L212 (28.1412, 13.1788) -> (28.2799, 13.3175)
  line L213 (28.2799, 13.3175) -> (28.4386, 13.4328)
  line L214 (28.4386, 13.4328) -> (28.6134, 13.5218)
  line L215 (28.6134, 13.5218) -> (28.7999, 13.5824)
  line L216 (28.7999, 13.5824) -> (28.9937, 13.6131)
  line L217 (28.9937, 13.6131) -> (29.0917, 13.617)
  line L218 (29.0917, 13.617) -> (29.5917, 13.617)
  line L219 (29.5917, 13.617) -> (29.6898, 13.6131)
  line L220 (37.3098, 13.6131) -> (37.5035, 13.5824)
  line L221 (37.5035, 13.5824) -> (37.6901, 13.5218)
  line L222 (37.6901, 13.5218) -> (37.8649, 13.4328)
  line L223 (37.8649, 13.4328) -> (38.0236, 13.3175)
  line L224 (38.0236, 13.3175) -> (38.1622, 13.1788)
  line L225 (38.1622, 13.1788) -> (38.2775, 13.0201)
  line L226 (38.2775, 13.0201) -> (38.3666, 12.8453)
  line L227 (38.3666, 12.8453) -> (38.4272, 12.6588)
  line L228 (38.4272, 12.6588) -> (38.4579, 12.465)
  line L229 (38.4579, 12.465) -> (38.4579, 12.2689)
  line L230 (38.4579, 12.2689) -> (38.4272, 12.0752)
  line L231 (38.4272, 12.0752) -> (38.3666, 11.8886)
  line L232 (38.3666, 11.8886) -> (38.2775, 11.7138)
  line L233 (38.2775, 11.7138) -> (38.1622, 11.5551)
  line L234 (38.1622, 11.5551) -> (38.0236, 11.4165)
  line L235 (38.0236, 11.4165) -> (37.8649, 11.3012)
  line L236 (37.8649, 11.3012) -> (37.6901, 11.2121)
  line L237 (37.6901, 11.2121) -> (37.5035, 11.1515)
  line L238 (37.5035, 11.1515) -> (37.3098, 11.1208)
  line L239 (37.3098, 11.1208) -> (37.2117, 11.117)
  line L240 (37.2117, 11.117) -> (36.7117, 11.117)
  line L241 (36.7117, 11.117) -> (36.6137, 11.1208)
  line L242 (36.6137, 11.1208) -> (36.4199, 11.1515)
  line L243 (36.4199, 11.1515) -> (36.2334, 11.2121)
  line L244 (36.2334, 11.2121) -> (36.0586, 11.3012)
  line L245 (36.0586, 11.3012) -> (35.8999, 11.4165)
  line L246 (35.8999, 11.4165) -> (35.7612, 11.5551)
  line L247 (35.7612, 11.5551) -> (35.6459, 11.7138)
  line L248 (35.6459, 11.7138) -> (35.5569, 11.8886)
  line L249 (35.5569, 11.8886) -> (35.4963, 12.0751)
  line L250 (35.4963, 12.0751) -> (35.4656, 12.2689)
  line L251 (35.4656, 12.2689) -> (35.4656, 12.465)
  line L252 (35.4656, 12.465) -> (35.4963, 12.6588)
  line L253 (35.4963, 12.6588) -> (35.5569, 12.8453)
  line L254 (35.5569, 12.8453) -> (35.6459, 13.0201)
  line L255 (35.6459, 13.0201) -> (35.7612, 13.1788)
  line L256 (35.7612, 13.1788) -> (35.8999, 13.3175)
  line L257 (35.8999, 13.3175) -> (36.0586, 13.4328)
  line L258 (36.0586, 13.4328) -> (36.2334, 13.5218)
  line L259 (36.2334, 13.5218) -> (36.4199, 13.5824)
  line L260 (36.4199, 13.5824) -> (36.6137, 13.6131)
  line L261 (36.6137, 13.6131) -> (36.7117, 13.617)
  line L262 (36.7117, 13.617) -> (37.2117, 13.617)
  line L263 (37.2117, 13.617) -> (37.3098, 13.6131)
  line L264 (90.6498, 13.6131) -> (90.8435, 13.5824)
  line L265 (90.8435, 13.5824) -> (91.0301, 13.5218)
  line L266 (91.0301, 13.5218) -> (91.2049, 13.4328)
  line L267 (91.2049, 13.4328) -> (91.3636, 13.3175)
  line L268 (91.3636, 13.3175) -> (91.5022, 13.1788)
  line L269 (91.5022, 13.1788) -> (91.6175, 13.0201)
  line L270 (91.6175, 13.0201) -> (91.7066, 12.8453)
  line L271 (91.7066, 12.8453) -> (91.7672, 12.6588)
  line L272 (91.7672, 12.6588) -> (91.7979, 12.465)
  line L273 (91.7979, 12.465) -> (91.7979, 12.2689)
  line L274 (91.7979, 12.2689) -> (91.7672, 12.0752)
  line L275 (91.7672, 12.0752) -> (91.7066, 11.8886)
  line L276 (91.7066, 11.8886) -> (91.6175, 11.7138)
  line L277 (91.6175, 11.7138) -> (91.5022, 11.5551)
  line L278 (91.5022, 11.5551) -> (91.3635, 11.4165)
  line L279 (91.3635, 11.4165) -> (91.2049, 11.3012)
  line L280 (91.2049, 11.3012) -> (91.0301, 11.2121)
  line L281 (91.0301, 11.2121) -> (90.8435, 11.1515)
  line L282 (90.8435, 11.1515) -> (90.6498, 11.1208)
  line L283 (90.6498, 11.1208) -> (90.5517, 11.117)
  line L284 (90.5517, 11.117) -> (90.0517, 11.117)
  line L285 (90.0517, 11.117) -> (89.9537, 11.1208)
  line L286 (89.9537, 11.1208) -> (89.7599, 11.1515)
  line L287 (89.7599, 11.1515) -> (89.5734, 11.2121)
  line L288 (89.5734, 11.2121) -> (89.3986, 11.3012)
  line L289 (89.3986, 11.3012) -> (89.2399, 11.4165)
  line L290 (89.2399, 11.4165) -> (89.1012, 11.5551)
  line L291 (89.1012, 11.5551) -> (88.9859, 11.7138)
  line L292 (88.9859, 11.7138) -> (88.8969, 11.8886)
  line L293 (88.8969, 11.8886) -> (88.8363, 12.0751)
  line L294 (88.8363, 12.0751) -> (88.8056, 12.2689)
  line L295 (88.8056, 12.2689) -> (88.8056, 12.465)
  line L296 (88.8056, 12.465) -> (88.8363, 12.6588)
  line L297 (88.8363, 12.6588) -> (88.8969, 12.8453)
  line L298 (88.8969, 12.8453) -> (88.9859, 13.0201)
  line L299 (88.9859, 13.0201) -> (89.1012, 13.1788)
  line L300 (89.1012, 13.1788) -> (89.2399, 13.3175)
  line L301 (89.2399, 13.3175) -> (89.3986, 13.4328)
  line L302 (89.3986, 13.4328) -> (89.5734, 13.5218)
  line L303 (89.5734, 13.5218) -> (89.7599, 13.5824)
  line L304 (89.7599, 13.5824) -> (89.9537, 13.6131)
  line L305 (89.9537, 13.6131) -> (90.0517, 13.617)
  line L306 (90.0517, 13.617) -> (90.5517, 13.617)
  line L307 (90.5517, 13.617) -> (90.6498, 13.6131)
  line L308 (98.2698, 13.6131) -> (98.4635, 13.5824)
  line L309 (98.4635, 13.5824) -> (98.6501, 13.5218)
  line L310 (98.6501, 13.5218) -> (98.8249, 13.4328)
  line L311 (98.8249, 13.4328) -> (98.9836, 13.3175)
  line L312 (98.9836, 13.3175) -> (99.1222, 13.1788)
  line L313 (99.1222, 13.1788) -> (99.2375, 13.0201)
  line L314 (99.2375, 13.0201) -> (99.3266, 12.8453)
  line L315 (99.3266, 12.8453) -> (99.3872, 12.6588)
  line L316 (99.3872, 12.6588) -> (99.4179, 12.465)
  line L317 (99.4179, 12.465) -> (99.4179, 12.2689)
  line L318 (99.4179, 12.2689) -> (99.3872, 12.0752)
  line L319 (99.3872, 12.0752) -> (99.3266, 11.8886)
  line L320 (99.3266, 11.8886) -> (99.2375, 11.7138)
  line L321 (99.2375, 11.7138) -> (99.1222, 11.5551)